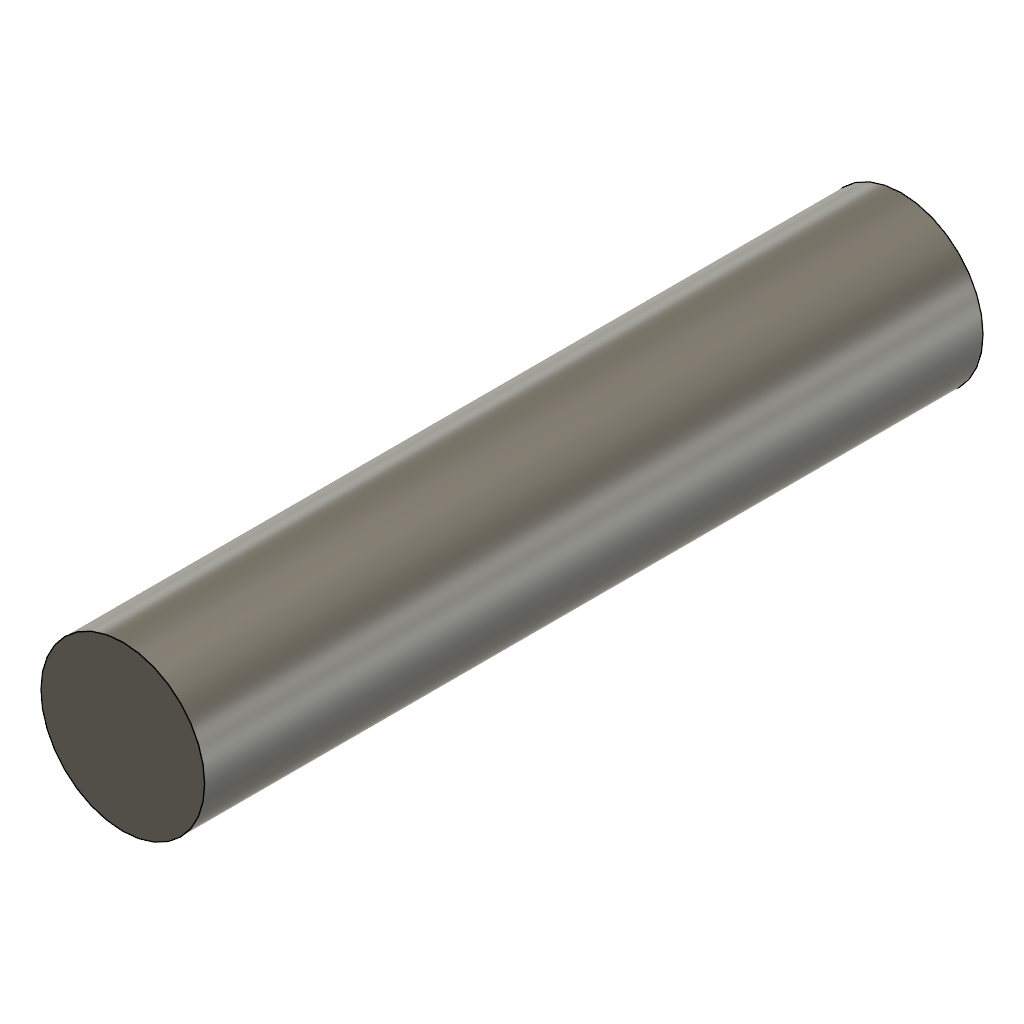
holdout_e_edit_second (Autodesk Fusion 360 design; units mm, degrees)
part number: 2026-11-27-17-36-54-849
Autodesk Fusion 360 part; units mm, degrees
sketch "CircularProfile" plane through (0, 0, 0) normal (0, 0, 1) x (1, 0, 0)
  circle A0 centre (-37, -13) radius 7.1
extrude "OffsetTwoSides" add sketch "CircularProfile" along normal blind 11.125 and the other way blind 56.375 from surface at -0.75
